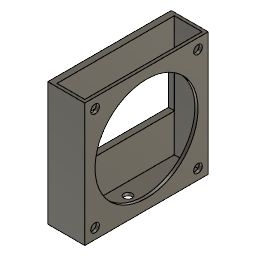
Lamp bracket (Autodesk Fusion 360 design; units mm, degrees)
Autodesk Fusion 360 part; units mm, degrees
sketch "Sketch5" plane through (0, 0, 0) normal (0, 0, 1) x (1, 0, 0)
  line L0 (0, 0) -> (60, 0)
  line L1 (60, 0) -> (60, 60)
  line L2 (60, 60) -> (0, 60)
  line L3 (0, 60) -> (0, 0)
  dimension "d14" = 60
  dimension "d15" = 60
  constraint horizontal L0
  constraint vertical L1
  constraint horizontal L2
  constraint vertical L3
  constraint coincident L0.start L3.end
  measures "d14" distance of L0.start L0.end
  measures "d15" distance of L0.start L2.end
extrude "Extrude5" add sketch "Sketch5" along normal blind 18
sketch "Sketch6" plane through (0, 0, 0) normal (0, 0, -1) x (1, 0, 0)
  line L0 (0, 0) -> (0, -60)
  line L1 (0, -60) -> (60, -60)
  line L2 (60, -60) -> (60, 0)
  line L3 (60, 0) -> (0, 0)
shell "Shell2" thickness 1.5 removed faces 1 at (20, 40, 0)
sketch "Sketch7" plane through (0, 0, 0) normal (0, 0, -1) x (1, 0, 0)
  line L0 (30, -60) -> (30, 0)
  line L1 (60, -30) -> (0, -30)
  line L2 (5, -5) -> (55, -5)
  line L3 (55, -5) -> (55, -55)
  line L4 (55, -55) -> (5, -55)
  line L5 (5, -55) -> (5, -5)
  line L6 (5, -5) -> (55, -55) construction
  line L7 (55, -5) -> (5, -55) construction
  circle A0 centre (55, -55) radius 2.1
  circle A1 centre (5, -55) radius 2.1
  circle A2 centre (5, -5) radius 2.1
  circle A3 centre (55, -5) radius 2.1
  point P0 (30, -30)
  dimension "d19" = 50
  dimension "d20" = 50
  dimension "d21" = 4.2
  dimension "d22" = 4.2
  dimension "d23" = 4.2
  dimension "d24" = 4.2
  constraint vertical L0
  constraint perpendicular L0 L1
  constraint horizontal L2
  constraint perpendicular L2 L3
  constraint parallel L2 L4
  constraint parallel L3 L5
  constraint coincident L6 P0
  constraint coincident L7 P0
  constraint midpoint L1 P0
  constraint coincident L3.end L4.start
  constraint coincident L4.end L5.start
  constraint coincident L2.start L5.end
  constraint coincident L2.end L3.start
  measures "d19" distance of L3.end L4.end
  measures "d20" distance of L2.end L3.end
  measures "d21" diameter of A0
  measures "d22" diameter of A1
  measures "d23" diameter of A2
  measures "d24" diameter of A3
extrude "Extrude6" cut sketch "Sketch7" against normal blind 454634436 contours L3 L4 A0 | L3 L4 A0 | L4 L5 A1 | L4 L5 A1 | L2 L5 A2 | L2 L5 A2 | L2 L3 A3 | L2 L3 A3
sketch "Sketch8" plane through (0, 0, 0) normal (0, 0, -1) x (1, 0, 0)
  line L0 (30, -60) -> (30, 0)
  line L1 (60, -30) -> (0, -30)
  circle A0 centre (30, -30) radius 25
  dimension "d27" = 50
  constraint vertical L0
  constraint perpendicular L0 L1
  constraint midpoint L0 A0.centre
  measures "d27" diameter of A0
extrude "Extrude7" cut sketch "Sketch8" against normal blind 435344436
extrude "Extrude8" add sketch "Sketch6" against normal blind 3
sketch "Sketch9" plane through (0, 0, 0) normal (0, 0, -1) x (1, 0, 0)
  line L0 (0, 0) -> (0, -60)
  line L1 (0, -60) -> (60, -60)
  line L2 (60, -60) -> (60, 0)
  line L3 (60, 0) -> (0, 0)
  line L4 (40.1, -58.65) -> (19.9, -58.65)
  line L5 (19.9, -58.65) -> (19.9, -1.35)
  line L6 (19.9, -1.35) -> (40.1, -1.35)
  line L7 (40.1, -1.35) -> (40.1, -58.65)
  line L8 (40.1, -58.65) -> (19.9, -1.35) construction
  line L9 (19.9, -58.65) -> (40.1, -1.35) construction
  point P0 (30, -30)
  dimension "d32" = 20.2
  dimension "d33" = 57.3
  constraint horizontal L4
  constraint perpendicular L4 L5
  constraint parallel L4 L6
  constraint parallel L5 L7
  constraint coincident L8 P0
  constraint coincident L9 P0
  measures "d32" distance of L5.end L6.end
  measures "d33" distance of L4.end L5.end
extrude "Extrude9" cut sketch "Sketch9" against normal blind 3 contours L4 L5 L6 L7
sketch "Sketch10" plane through (0, 0, 0) normal (-1, 0, 0) x (0, -1, 0)
  line L0 (0, 0) -> (0, 18)
  line L1 (0, 18) -> (-60, 18)
  line L2 (-60, 18) -> (-60, 0)
  line L3 (-60, 0) -> (0, 0)
  line L4 (-60, 9) -> (-58.5, 9)
  line L5 (0, 9) -> (-1.5, 9)
  line L6 (-1.5, 18) -> (-1.5, 16.5)
  line L7 (-1.5, 16.5) -> (-58.5, 16.5)
  line L8 (-58.5, 16.5) -> (-58.5, 3)
  line L9 (-58.5, 3) -> (-1.5, 3)
  line L10 (-1.5, 3) -> (-1.5, 16.5)
  dimension "d36" = 1.5
  dimension "d37" = 1.5
  dimension "d38" = 1.5
  dimension "d39" = 13.5
  constraint midpoint L2 L4.start
  constraint horizontal L4
  constraint midpoint L0 L5.start
  constraint horizontal L5
  constraint coincident L1 L6.start
  constraint perpendicular L5 L6
  constraint horizontal L7
  constraint vertical L8
  constraint horizontal L9
  constraint vertical L10
  measures "d36" distance of L4.start L4.end
  measures "d37" distance of L5.start L5.end
  measures "d38" distance of L6.start L6.end
  measures "d39" distance of L6.end L9.end
extrude "Extrude10" cut sketch "Sketch10" against normal blind 1.5 contours L7 L8 L9 L10
move_body "Move1" bodies 1 to x (0, 0, -1) y (0, 1, 0) z (1, 0, 0) at (21, 0, 60)
sketch "Sketch11" plane through (0, 0, 0) normal (0, 0, -1) x (1, 0, 0)
  line L0 (21, -60) -> (39, -60)
  line L1 (39, -60) -> (39, 0)
  line L2 (39, 0) -> (21, 0)
  line L3 (21, 0) -> (21, -60)
  line L4 (30, 0) -> (30, -60)
  line L5 (39, -30) -> (21, -30)
  circle A0 centre (30, -30) radius 2
  dimension "d42" = 4
  constraint midpoint L2 L4.start
  constraint midpoint L0 L4.end
  constraint midpoint L1 L5.start
  constraint midpoint L3 L5.end
  constraint midpoint L5 A0.centre
  measures "d42" diameter of A0
extrude "Extrude11" cut sketch "Sketch11" against normal blind 786765765 contours L4 L5 A0 | L4 L5 A0 | L4 L5 A0 | L4 L5 A0
